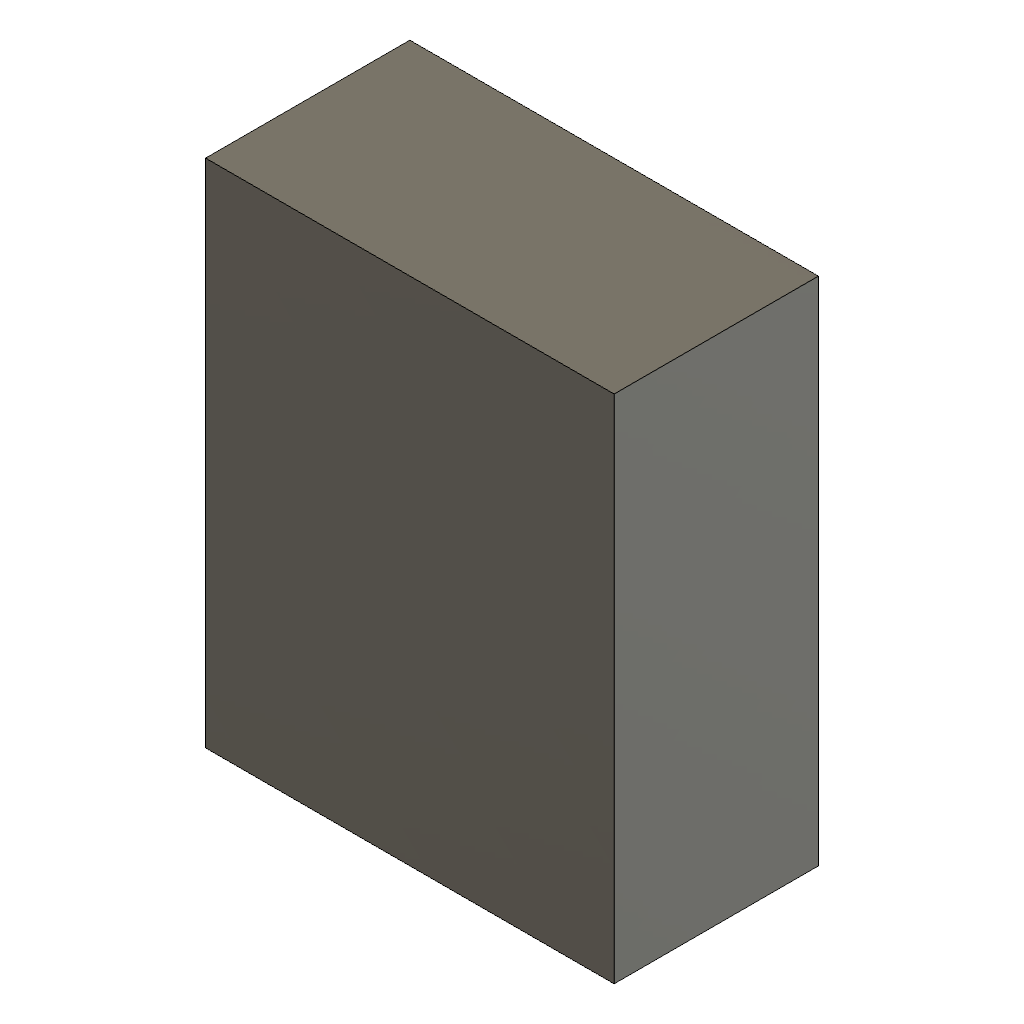
translated_unequal_rectangles (Autodesk Fusion 360 design; units mm, degrees)
part number: 2026-10-21-12-03-45-354
Autodesk Fusion 360 part; units mm, degrees
sketch "TrimmedProfileSources" plane through (0, 0, 0) normal (0, 0, 1) x (1, 0, 0)
  line L0 (10, 20) -> (70, 20)
  line L1 (70, 20) -> (70, 60)
  line L2 (70, 60) -> (10, 60)
  line L3 (10, 60) -> (10, 20)
  line L4 (50, 0) -> (90, 0)
  line L5 (90, 0) -> (90, 45)
  line L6 (90, 45) -> (50, 45)
  line L7 (50, 45) -> (50, 0)
extrude "SelectedTrimmedProfile" add sketch "TrimmedProfileSources" along normal blind 10 contours L0 L1 L6 L7
